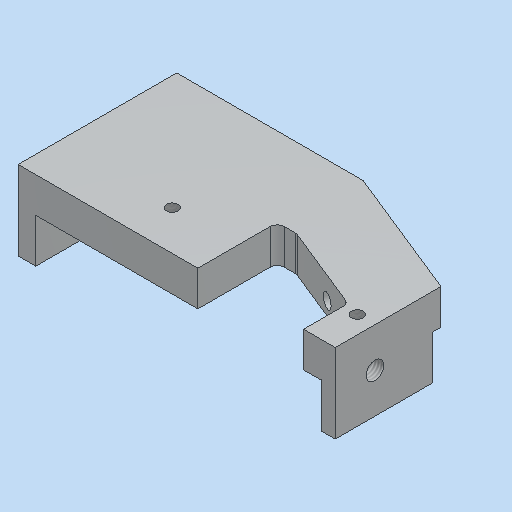
# Autodesk Inventor part: SE0004AN000_G01_354
Saved by Autodesk Inventor 2023.3 (Build 273359000, 359)
## iProperties
RuleStatus: InUse
Created: 2021-10-07
Part Number: SE0004AN000_G01_354
Material: 3.3547 AlMg4,5Mn0,7 - AW 5083
Description: =<RBPARTNOTITLE2>
Document SubType Name: Modeling
Designer: brt9bw
Mass: 687.109 g
Surface Area: 496.841 cm^2
Volume: 258.312 cm^3
Density: 2.66 g/cm^3
Appearance: Aluminium AnP
AnP_Kategorie: 1
AnP_Material: =<Material>
MaxAbmaße: 45 x 90 x 180 (FM)
AnP_TemplVers: 20200821
RBDOCUMENTTYPE: DRF
RBDOCUMENTVERSION: 00
RBDRAWINGMAINSCALE: 1:1
RBDRAWINGMISSINGSPEC: --
RBDRAWINGVOLUME: --
RBDSV1: 0850
RBGBEDGESIN1: +0,5
RBGBEDGESIN2: +0,2
RBGBEDGESOUT1: -0,3
RBGBEDGESOUT2: -0,1
RBMATERIAL: =<Material>
RBMATMEETS: --
RBMATNO: =<Part Number>
RBPARTMADEOF: 45 x 90 x 180 (FM)
RBPARTNO: SIEHE MNR
RBPARTNOTITLE1: manufactured part
RBPARTNOTITLE2: Anfertigungsteil
RBPARTSAFETYINDICATOR: --
RBSURFACE: anodised colourless
RBSURFACE2: eloxiert farblos
RBZEDGESNORM: ISO13715:2002-06
RBZGENDIMCLASS: m
RBZGENDIMNORM: ISO 2768-1:1989-11
RBZGENGEOCLASS: H
RBZGENGEONORM: ISO 2768-2:1989-11
RBZSURFACENORM: ISO13D2:2002-02
RBZTOLERANCENORM: ISO 14405-1:2010-12
Author: brt9bw
Keywords: =<RBPARTMADEOF>
Comments: =<RBSURFACE2>
Revision Number: 01
Autodesk Inventor part; units mm, degrees
ref_plane "YZ Plane" through (0, 0, 0) normal (1, 0, 0) x (0, 1, 0)
ref_plane "XZ Plane" through (0, 0, 0) normal (0, 1, 0) x (-1, 0, 0)
ref_plane "XY Plane" through (0, 0, 0) normal (0, 0, 1) x (1, 0, 0)
sketch "Skizze1" plane through (0, 0, 0) normal (0, 0, 1) x (1, 0, 0)
  line L0 (0, 0) -> (180, 0)
  line L1 (180, 0) -> (180, 90)
  line L2 (180, 90) -> (0, 90)
  line L3 (0, 90) -> (0, 0)
  dimension "d0" = 180
  dimension "d1" = 90
  constraints: 8 end point, 2 parallel, 1 horizontal, 1 perpendicular
  measures "d0" distance of L2.end L1.end
  measures "d1" distance of L1.end L0.end
extrude "Extrusion1" add sketch "Skizze1" against normal blind 45
sketch "Skizze2" plane through (0, 0, 0) normal (0, 0, 1) x (1, 0, 0)
  line L0 (180, 0) -> (180, 90) projected
  line L1 (180, 90) -> (0, 90) projected
  line L2 (0, 90) -> (0, 0) projected
  line L3 (0, 0) -> (180, 0) projected
  line L4 (180, 60) -> (105.7474, 90)
  dimension "d4" = 68
  dimension "d5" = 60
  constraints: 2 end point, 2 point on line
  measures "d4" angle of L0 L4
  measures "d5" distance from line of L4.start L3
extrude "Extrusion2" cut sketch "Skizze2" against normal through all contours L4 L1 L0
sketch "Skizze3" plane through (0, 0, 0) normal (0, 0, 1) x (1, 0, 0)
  line L0 (180, 60) -> (105.7474, 90) projected
  line L1 (105.7474, 90) -> (0, 90) projected
  line L2 (0, 90) -> (0, 0) projected
  line L3 (0, 0) -> (180, 0) projected
  line L4 (180, 0) -> (180, 60) projected
  line L5 (162, 25.2096) -> (113.0171, 45)
  line L6 (113.0171, 45) -> (102, 45)
  line L7 (102, 45) -> (102, 0)
  line L8 (102, 0) -> (162, 0)
  line L9 (162, 0) -> (162, 25.2096)
  line L10 (0, 0) -> (180, 0) projected
  dimension "d9" = 39
  dimension "d11" = 60
  dimension "d54" = 18
  dimension "d55" = 45
  constraints: 10 end point, 2 horizontal, 2 perpendicular, 1 collinear, 1 parallel
  measures "d9" distance between parallel lines of L0 L5
  measures "d11" distance between parallel lines of L9 L7
  measures "d54" distance between parallel lines of L4 L9
  measures "d55" distance of L6.end L7.end
extrude "Extrusion3" cut sketch "Skizze3" against normal through all contours L3 L7 L6 L5 L9
sketch "Skizze4" plane through (0, 0, 0) normal (0, -1, 0) x (1, 0, 0)
  line L0 (0, 0) -> (102, 0) projected
  line L1 (0, 0) -> (0, -45) projected
  line L2 (180, -45) -> (162, -45) projected
  line L3 (180, 0) -> (180, -45) projected
  line L4 (10, -45) -> (172, -45)
  line L5 (172, -45) -> (172, -20)
  line L6 (172, -20) -> (10, -20)
  line L7 (10, -20) -> (10, -45)
  line L8 (162, 0) -> (162, -45) projected
  line L9 (162, 0) -> (180, 0) projected
  line L10 (102, -45) -> (102, 0) projected
  line L11 (102, -45) -> (0, -45) projected
  point P0 (162, -20)
  dimension "d15" = 8
  dimension "d16" = 10
  dimension "d17" = 25
  constraints: 8 end point, 2 parallel, 1 horizontal, 1 perpendicular, 1 point on line
  measures "d15" distance between parallel lines of L3 L5
  measures "d16" distance between parallel lines of L1 L7
  measures "d17" distance between parallel lines of L2 L6
extrude "Extrusion4" cut sketch "Skizze4" against normal through all contours L10 L4 L7 L6 | L6 L8 L4 L10 | L6 L5 L2 L8
sketch "Skizze5" plane through (180, 60, 0) normal (0.3746066, 0.9271839, 0) x (0.9271839, -0.3746066, 0)
  line L0 (-8.6283, 20) -> (-80.084, 20) projected
  line L1 (0, 45) -> (0, 0) projected
  point P0 (-144.4167, 0)
  point P1 (-25, 12.5)
  point P2 (-21.5707, 20)
  dimension "d20" = 7.5
  dimension "d21" = 25
  measures "d20" distance from line of point (-25, 12.5) L0
  measures "d21" distance from line of point (-25, 12.5) L1
hole "Bohrung1" at (156.8204, 69.3652, -12.5) direction (-0.3746066, -0.9271839, 0) diameter 8 depth 39
sketch "Skizze6" plane through (180, 0, 0) normal (1, 0, 0) x (0, 0, -1)
  line L0 (0, 0) -> (45, 0) projected
  line L1 (45, 60) -> (45, 0) projected
  point P0 (22.5, 22.5)
  dimension "d29" = 22.5
  dimension "d30" = 22.5
  measures "d29" distance from line of point (22.5, 22.5) L0
  measures "d30" distance from line of point (22.5, 22.5) L1
hole "Bohrung2" at (180, 22.5, -22.5) direction (-1, 0, 0) diameter 10.106 depth 20.3 tip angle 118 thread size "M12x1.75" designation "M12" class "6H" standard "ISO Metric profile"
sketch "Skizze7" plane through (0, 0, 0) normal (-1, 0, 0) x (0, 0, 1)
  line L0 (0, 90) -> (0, 0) projected
  line L1 (0, 90) -> (-45, 90) projected
  line L2 (-45, 0) -> (-45, 90) projected
  line L3 (0, 0) -> (-45, 0) projected
  point P0 (-22.5, 22.5)
  point P1 (-22.5, 67.5)
  dimension "d38" = 45
  dimension "d39" = 22.5
  dimension "d40" = 22.5
  constraints: 1 vertical alignment
  measures "d38" distance of point (-22.5, 22.5) point (-22.5, 67.5)
  measures "d39" distance from line of L1 point (-22.5, 67.5)
  measures "d40" distance from line of point (-22.5, 67.5) L2
hole "Bohrung3" at (0, 22.5, -22.5) at (0, 67.5, -22.5) direction (1, 0, 0) diameter 13.5 depth 10 clearance for "Inbusschraube ISO 4762  versenkt" size "M12" standard "ISO"
sketch "Skizze8" plane through (172, 0, -20) normal (0, 0, -1) x (-1, 0, 0)
  line L0 (58.9829, 45) -> (12.6192, 26.2678) projected
  line L1 (70, 45) -> (58.9829, 45) projected
  line L2 (70, 0) -> (70, 45) projected
  line L3 (162, 28.77) -> (162, 61.23) projected
  line L4 (162, 73.77) -> (162, 90) projected
  line L5 (66.2526, 90) -> (162, 90) projected
  line L6 (0, 63.2322) -> (66.2526, 90) projected
  line L7 (0, 26.8912) -> (12.3, 26.8912) projected
  line L8 (10, 18.1088) -> (0, 18.1088) projected
  line L9 (10, 0) -> (0, 0) projected
  line L10 (162, 0) -> (162, 16.23) projected
  line L11 (162, 82) -> (127, 82)
  line L12 (127, 82) -> (127, 8)
  line L13 (127, 8) -> (162, 8)
  line L14 (162, 8) -> (162, 82)
  line L15 (0, 26.8912) -> (0, 63.2322) projected
  line L16 (0, 0) -> (0, 18.1088) projected
  line L17 (10, 18.1088) -> (10, 0) projected
  line L18 (162, 0) -> (70, 0) projected
  point P0 (172, 0)
  dimension "d48" = 8
  dimension "d49" = 8
  dimension "d50" = 35
  constraints: 8 end point, 2 parallel, 2 vertical alignment, 1 horizontal, 1 perpendicular, 1 point on line, 1 other
  measures "d48" distance between parallel lines of L5 L11
  measures "d49" distance between parallel lines of L9 L13
  measures "d50" distance between parallel lines of L12 L14
extrude "Extrusion5" cut sketch "Skizze8" against normal blind 10 contours L14 L10 L13 L12 L11 L4 L3
fillet "Rundung1" radius 4 7 edges at (45, 8, -15) (45, 82, -15) (10, 82, -15) (10, 8, -15) (102, 45, -10) (113.0171, 45, -10) (162, 25.2096, -9.1175)
sketch "Skizze9" plane through (0, 0, -45) normal (0, 0, -1) x (-1, 0, 0)
  line L0 (-172, 0) -> (-172, 63.2322) projected
  line L1 (-172, 63.2322) -> (-180, 60) projected
  line L2 (-180, 60) -> (-180, 0) projected
  line L3 (-180, 0) -> (-172, 0) projected
  line L4 (-180, 55) -> (-172, 55)
  point P0 (0, 0)
  dimension "d56" = 5
  constraints: 2 end point, 2 point on line, 1 horizontal
  measures "d56" distance of L4.start L1.end
extrude "Extrusion6" cut sketch "Skizze9" against normal up to surface (25 mm away) contours L4 L2 L1 L0
sketch "Skizze10" plane through (0, 0, 0) normal (0, 0, 1) x (1, 0, 0)
  line L0 (162, 22.5116) -> (162, 0) projected
  line L1 (162, 0) -> (180, 0) projected
  line L2 (180, 0) -> (180, 60) projected
  line L3 (180, 60) -> (105.7474, 90) projected
  line L4 (105.7474, 90) -> (0, 90) projected
  line L5 (0, 90) -> (0, 0) projected
  line L6 (0, 0) -> (102, 0) projected
  line L7 (102, 0) -> (102, 41) projected
  arc A0 (106, 45) -> (102, 41) centre (106, 41) ccw projected
  line L8 (106, 45) -> (112.2396, 45) projected
  arc A1 (113.738, 44.7087) -> (112.2396, 45) centre (112.2396, 41) ccw projected
  line L9 (113.738, 44.7087) -> (159.4984, 26.2203) projected
  arc A2 (162, 22.5116) -> (159.4984, 26.2203) centre (158, 22.5116) ccw projected
  point P0 (65, 22.5)
  point P1 (170, 22.5)
  dimension "d59" = 22.5
  dimension "d60" = 105
  dimension "d61" = 10
  constraints: 1 horizontal alignment
  measures "d59" distance from line of point (65, 22.5) L6
  measures "d60" distance of point (170, 22.5) point (65, 22.5)
  measures "d61" distance from line of L2 point (170, 22.5)
hole "Bohrung4" at (65, 22.5, 0) at (170, 22.5, 0) direction (0, 0, -1) diameter 6.647 depth 22.2 tip angle 118 thread size "M8x1.25" designation "M8" class "6H" standard "ISO Metric profile"
